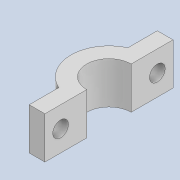
# Autodesk Inventor part: крепление 2
Saved by Autodesk Inventor 2021.2 (Build 252289000, 289)
## iProperties
Created: 2026-11-16
Part Number: крепление 2
Material: Типовые
Document SubType Name: Modeling
Designer: ritar
Density: 1 g/cm^3
Appearance: По умолчанию
Author: ritar
Autodesk Inventor part; units mm, degrees
ref_plane "YZ Plane" through (0, 0, 0) normal (1, 0, 0) x (0, 1, 0)
ref_plane "XZ Plane" through (0, 0, 0) normal (0, 1, 0) x (-1, 0, 0)
ref_plane "XY Plane" through (0, 0, 0) normal (0, 0, 1) x (1, 0, 0)
sketch "Эскиз1" plane through (0, 0, 0) normal (0, 1, 0) x (-1, 0, 0)
  circle A0 centre (0, 0) radius 4.25
  line L0 (0, 4.25) -> (0, 12.25)
  line L1 (0, -4.25) -> (0, -12.25)
  line L2 (0, 12.25) -> (3, 12.25)
  line L3 (0, -12.25) -> (3, -12.25)
  line L4 (3, 12.25) -> (3, 6.6002)
  circle A1 centre (0, 0) radius 7.25
  line L5 (3, -12.25) -> (3, -6.6002)
  point P0 (3, -3.8615)
  dimension "d0" = 8.5
  dimension "d1" = 8
  dimension "d2" = 8
  dimension "d3" = 3
  dimension "d4" = 3
  dimension "d11" = 3
  dimension "d12" = 14.5
  dimension "d13" = 8.3885
  constraints: 12 end point, 4 point on circle, 4 vertical, 2 centre point, 2 horizontal, 2 vertical alignment, 1 coincident, 1 point on line
  measures "d0" diameter of A0
  measures "d1" distance of L0.start L0.end
  measures "d2" distance of L1.start L1.end
  measures "d3" distance of L0.end L2.end
  measures "d4" distance of L1.end L3.end
  measures "d11" radial gap between concentric circles of A0 A1
  measures "d12" diameter of A1
  measures "d13" distance of point (3, -3.862) L3.end
extrude "Выдавливание2" add sketch "Эскиз1" along normal blind 8 contours A0 L0 A1 L1 | L0 L2 L4 A1 | A1 L5 L3 L1 picked at (6.1515, -0.8634)
sketch "Эскиз3" plane through (-3, 0, 6.6002) normal (-1, 0, 0) x (0, 0, 1)
  circle A0 centre (-15.8502, 4) radius 1.5
  line L0 (-18.8502, 0) -> (-18.8502, 8) projected
  line L1 (-18.8502, 0) -> (-13.2004, 0) projected
  circle A1 centre (2.6498, 4) radius 1.5
  line L2 (5.6498, 0) -> (5.6498, 8) projected
  line L3 (0, 0) -> (5.6498, 0) projected
  point P0 (-6.6002, 0)
  dimension "d16" = 3
  dimension "d17" = 3
  dimension "d18" = 4
  dimension "d19" = 3
  dimension "d20" = 3
  dimension "d21" = 4
  constraints: 2 centre point
  measures "d16" diameter of A0
  measures "d17" distance from line of L0 A0.centre
  measures "d18" distance from line of L1 A0.centre
  measures "d19" diameter of A1
  measures "d20" distance from line of L2 A1.centre
  measures "d21" distance from line of L3 A1.centre
extrude "Выдавливание3" cut sketch "Эскиз3" against normal blind 8
